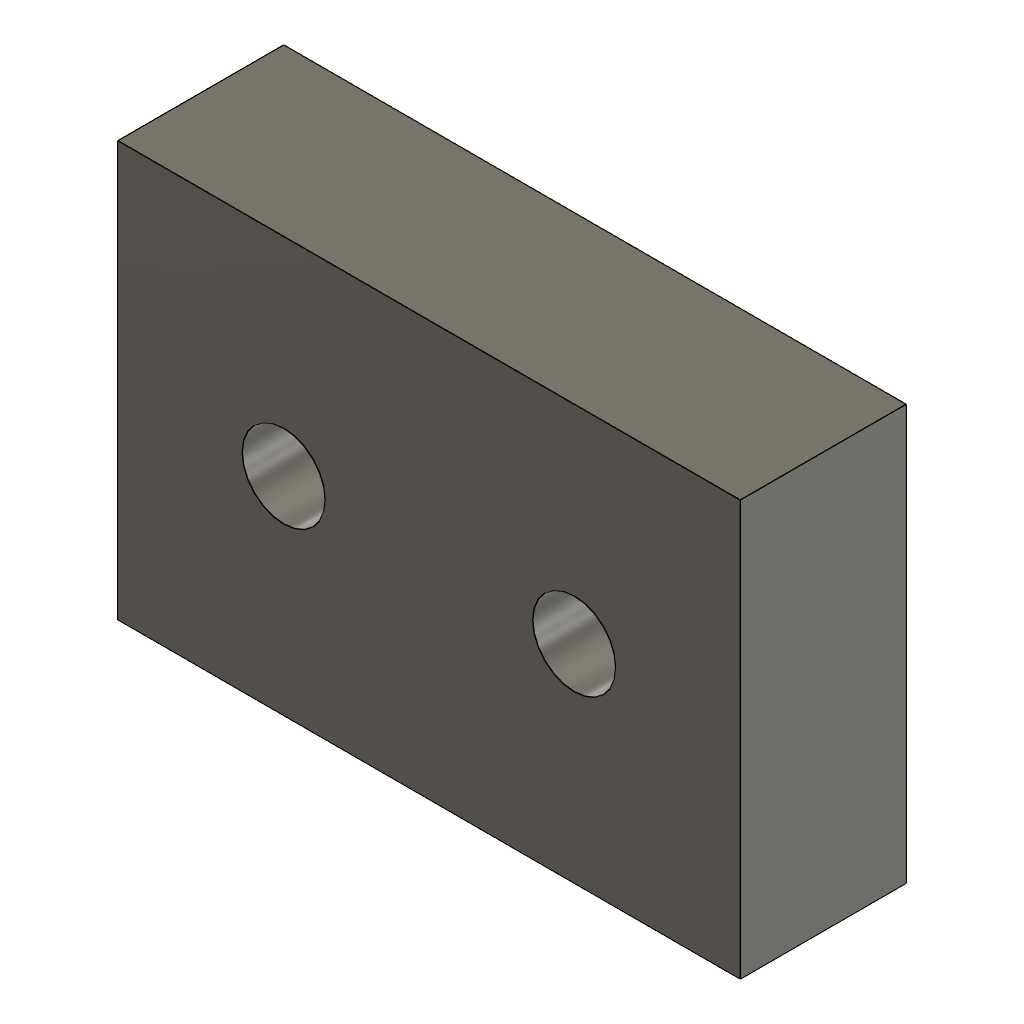
hole_two_points_on_face (Autodesk Fusion 360 design; units mm, degrees)
part number: 2026-11-13-14-39-56-069
Autodesk Fusion 360 part; units mm, degrees
sketch "Sketch1" plane through (0, 0, 0) normal (0, 0, 1) x (1, 0, 0)
  line L0 (0, 0) -> (30, 0)
  line L1 (30, 0) -> (30, 20)
  line L2 (30, 20) -> (0, 20)
  line L3 (0, 20) -> (0, 0)
extrude "Extrude1" add sketch "Sketch1" along normal blind 8
sketch "Sketch2" plane through (0, 0, 8) normal (0, 0, 1) x (1, 0, 0)
  line L0 (0, 20) -> (0, 0)
  line L1 (0, 0) -> (30, 0)
  line L2 (30, 0) -> (30, 20)
  line L3 (30, 20) -> (0, 20)
  point P0 (8, 10)
  point P1 (22, 10)
hole "Hole1" at (8, 10, 8) at (22, 10, 8) direction (0, 0, -1) diameter 4 depth 4 tip angle 118
